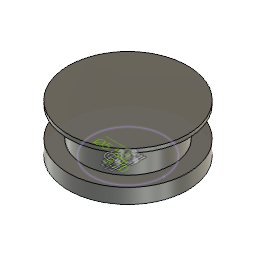
Seilspule5.5x3.7 (Autodesk Fusion 360 design; units mm, degrees)
Autodesk Fusion 360 part; units mm, degrees
sketch "Skizze1" plane through (0, 0, 0) normal (1, 0, 0) x (0, 1, 0)
  line L0 (0, 0) -> (0, 32.5)
  line L1 (0, 32.5) -> (40, 32.5)
  line L2 (40, 32.5) -> (40, 30)
  line L3 (40, 30) -> (30, 30)
  line L4 (30, 30) -> (30, 10)
  line L5 (30, 10) -> (40, 10)
  line L6 (40, 10) -> (40, 0)
  line L7 (24, 0) -> (24, 24)
  line L8 (24, 24) -> (7, 24)
  line L9 (7, 24) -> (7, 0)
  line L10 (40, 0) -> (24, 0)
  line L11 (7, 0) -> (0, 0)
  dimension "d3" = 30
  dimension "d4" = 40
  dimension "d5" = 20
  dimension "d6" = 2.5
  dimension "d7" = 10
  constraint coincident L0.start L11.end
  constraint vertical L0
  constraint perpendicular L0 L1
  constraint perpendicular L1 L2
  constraint perpendicular L2 L3
  constraint perpendicular L3 L4
  constraint perpendicular L4 L5
  constraint perpendicular L5 L6
  constraint perpendicular L0 L11
  constraint collinear L2 L6
  constraint perpendicular L7 L10
  constraint perpendicular L7 L8
  constraint perpendicular L9 L11
  constraint collinear L10 L11
  measures "d3" distance of L0 L4
  measures "d4" distance of L0.end L1.end
  measures "d5" distance of L3.end L4.end
  measures "d6" distance of L1.end L2.end
  measures "d7" distance of L5.end L6.end
revolve "Drehen1" add sketch "Skizze1" angle 360 about axis through (0, 0, 0) along (0, 0, 1)
sketch "Skizze2" plane through (0, 0, 0) normal (0, 0, -1) x (1, 0, 0)
  circle A0 centre (0, 0) radius 40
  line L0 (-1.85, -2.0347) -> (-1.85, 2.0347)
  line L1 (0, -4.2235) -> (0, 6.8272) construction
  line L2 (1.85, -2.0347) -> (1.85, 2.0347)
  arc A1 (1.85, 2.0347) -> (-1.85, 2.0347) centre (0, 0) ccw
  arc A2 (-1.85, -2.0347) -> (1.85, -2.0347) centre (0, 0) ccw
  circle A3 centre (0, 0) radius 24
  line L3 (-4.3533, 0) -> (4.9681, 0) construction
  dimension "d8" = 5.5
  dimension "d9" = 3.7
  constraint concentric A0 A1
  constraint vertical L0
  constraint vertical L1
  constraint coincident A0.centre L1
  constraint symmetric L0.start L1 L2.start
  constraint symmetric L0.end L1 L2.end
  constraint concentric A1 A2
  constraint symmetric A1 A2 L3
  constraint horizontal L3
  measures "d8" diameter of A1
  measures "d9" distance of L0 L2
extrude "Extrusion1" [rolled back] along distance -7 taper angle 0
sketch "Skizze3" plane through (0, 0, 30) normal (0, 0, -1) x (1, 0, 0)
  circle A0 centre (0, 0) radius 40
  circle A1 centre (0, 0) radius 30
  point P0 (0, -35)
  dimension "d12" = 35
  measures "d12" distance of A0.centre P0
hole "Bohrung1" [rolled back] hole depth 5 hole diameter 3 tip angle 118
fillet "Abrundung1" [rolled back] radius 2 radius 4 radius 1 radius 0.5
